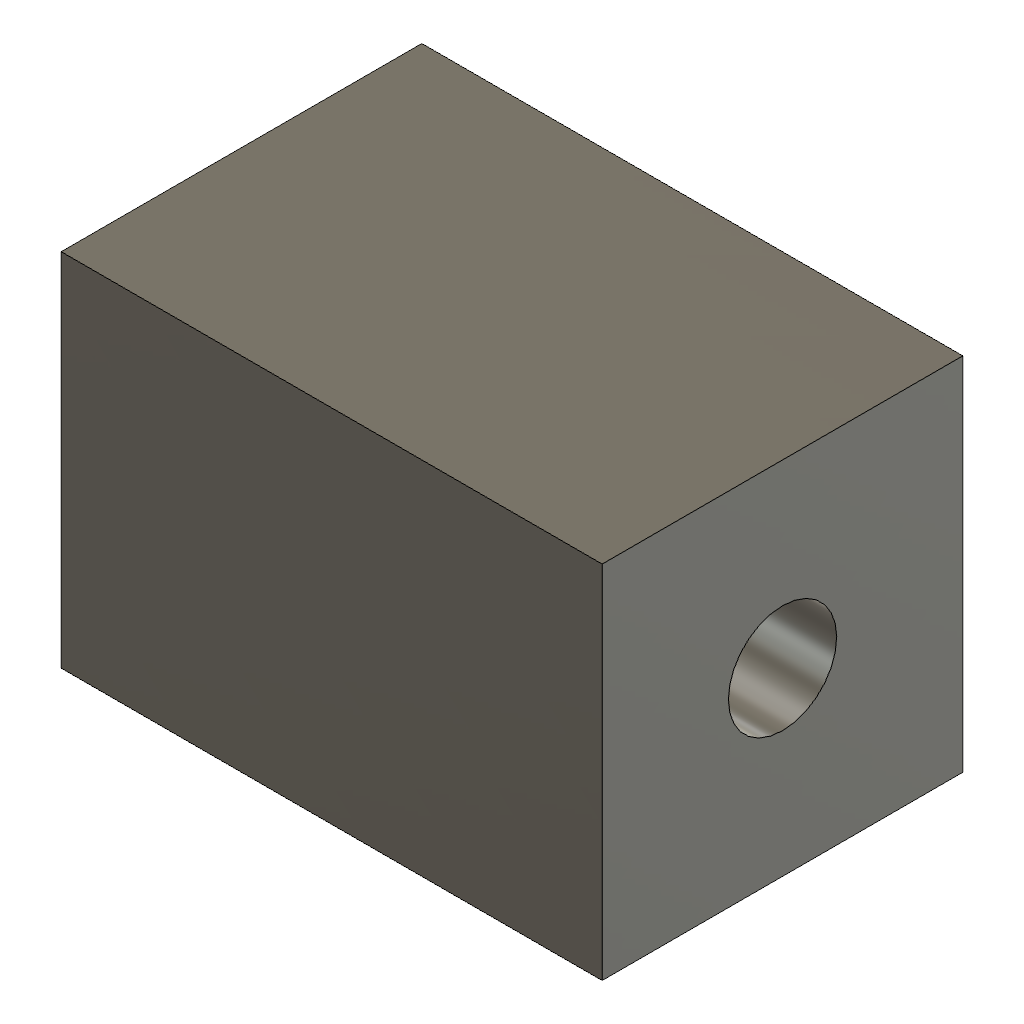
cut (Autodesk Fusion 360 design; units mm, degrees)
part number: 2026-10-21-12-27-08-252
Autodesk Fusion 360 part; units mm, degrees
ref_plane "WorkPlane1" through (0, 0, -10) normal (0, 0, 1) x (1, 0, 0)
sketch "PipeTargetProfile" plane through (0, 0, -10) normal (0, 0, 1) x (1, 0, 0)
  line L0 (0, -10) -> (30, -10)
  line L1 (30, -10) -> (30, 10)
  line L2 (30, 10) -> (0, 10)
  line L3 (0, 10) -> (0, -10)
extrude "PipeTargetExtrude" add sketch "PipeTargetProfile" along normal blind 20
sketch "PipeOperationPathSketch" plane through (0, 0, 0) normal (0, 0, 1) x (1, 0, 0)
  line L0 (-10, 0) -> (40, 0)
pipe "ProbePipeOperation_cut" cut diameter 6 path "PipeOperationPathSketch" along L0
named bodies: "PipeOperationTarget"
